Autodesk Fusion 360 part; units mm, degrees
(part 2 of 7)
sketch "Lower arm sketch" plane through (0, 0, 5) normal (0, 0, 1) x (1, 0, 0) in component "PRINT vertical alignment key B"
  line L0 (113, 68) -> (122, 68)
  line L1 (122, 68) -> (122, 72)
  line L2 (122, 72) -> (113, 72)
  line L3 (113, 72) -> (113, 68)
  dimension "d465" = 113
  dimension "d466" = 68
  dimension "d467" = 9
  dimension "d468" = 4
  constraint horizontal L0
  constraint vertical L1
  constraint horizontal L2
  constraint vertical L3
  measures "d465" horizontal distance of origin L0.start
  measures "d466" vertical distance of origin L0.start
  measures "d467" horizontal distance of L0.start L0.end
  measures "d468" vertical distance of L0.end L1.end
extrude "Lower arm" add sketch "Lower arm sketch" along normal blind 2 bodies 7 in component "PRINT vertical alignment key B"
ref_plane "WorkPlane3" through (0, 0, 5) normal (0, 0, 1) x (1, 0, 0) in component "PRINT vertical alignment key B"
sketch "Upper arm sketch" plane through (0, 0, 5) normal (0, 0, 1) x (1, 0, 0) in component "PRINT vertical alignment key B"
  line L0 (118, 78) -> (127, 78)
  line L1 (127, 78) -> (127, 82)
  line L2 (127, 82) -> (118, 82)
  line L3 (118, 82) -> (118, 78)
  dimension "d473" = 118
  dimension "d474" = 78
  dimension "d475" = 9
  dimension "d476" = 4
  constraint horizontal L0
  constraint vertical L1
  constraint horizontal L2
  constraint vertical L3
  measures "d473" horizontal distance of origin L0.start
  measures "d474" vertical distance of origin L0.start
  measures "d475" horizontal distance of L0.start L0.end
  measures "d476" vertical distance of L0.end L1.end
extrude "Upper arm" add sketch "Upper arm sketch" along normal blind 2 bodies 7 in component "PRINT vertical alignment key B"
ref_plane "WorkPlane4" through (0, 0, 5) normal (0, 0, 1) x (1, 0, 0) in component "PRINT vertical alignment key B"
sketch "Locating peg sketch (3)" plane through (0, 0, 5) normal (0, 0, 1) x (1, 0, 0) in component "PRINT vertical alignment key B"
  circle A0 centre (115, 70) radius 1.5
  dimension "d481" = 115
  dimension "d482" = 70
  dimension "d483" = 3
  measures "d481" horizontal distance of origin A0.centre
  measures "d482" vertical distance of origin A0.centre
  measures "d483" diameter of A0
extrude "Locating peg''" add sketch "Locating peg sketch (3)" against normal blind 0.8 bodies 7 in component "PRINT vertical alignment key B"
ref_plane "WorkPlane5" through (0, 0, 5) normal (0, 0, 1) x (1, 0, 0) in component "PRINT vertical alignment key B"
sketch "Locating peg sketch (1) (3)" plane through (0, 0, 5) normal (0, 0, 1) x (1, 0, 0) in component "PRINT vertical alignment key B"
  circle A0 centre (125, 80) radius 1.5
  dimension "d488" = 125
  dimension "d489" = 80
  dimension "d490" = 3
  measures "d488" horizontal distance of origin A0.centre
  measures "d489" vertical distance of origin A0.centre
  measures "d490" diameter of A0
extrude "Locating peg (1)''" add sketch "Locating peg sketch (1) (3)" against normal blind 0.8 bodies 7 in component "PRINT vertical alignment key B"
ref_plane "WorkPlane1" through (0, 0, 5) normal (0, 0, 1) x (1, 0, 0) in component "PRINT vertical alignment key T"
sketch "Key spine sketch (2)" plane through (0, 0, 5) normal (0, 0, 1) x (1, 0, 0) in component "PRINT vertical alignment key T"
  line L0 (118, 188) -> (122, 188)
  line L1 (122, 188) -> (122, 202)
  line L2 (122, 202) -> (118, 202)
  line L3 (118, 202) -> (118, 188)
  dimension "d495" = 118
  dimension "d496" = 188
  dimension "d497" = 4
  dimension "d498" = 14
  constraint horizontal L0
  constraint vertical L1
  constraint horizontal L2
  constraint vertical L3
  measures "d495" horizontal distance of origin L0.start
  measures "d496" vertical distance of origin L0.start
  measures "d497" horizontal distance of L0.start L0.end
  measures "d498" vertical distance of L0.end L1.end
extrude "Key spine'" add sketch "Key spine sketch (2)" along normal blind 2 separate body makes body 8 in component "PRINT vertical alignment key T"
ref_plane "WorkPlane2" through (0, 0, 5) normal (0, 0, 1) x (1, 0, 0) in component "PRINT vertical alignment key T"
sketch "Lower arm sketch (2)" plane through (0, 0, 5) normal (0, 0, 1) x (1, 0, 0) in component "PRINT vertical alignment key T"
  line L0 (113, 188) -> (122, 188)
  line L1 (122, 188) -> (122, 192)
  line L2 (122, 192) -> (113, 192)
  line L3 (113, 192) -> (113, 188)
  dimension "d503" = 113
  dimension "d504" = 188
  dimension "d505" = 9
  dimension "d506" = 4
  constraint horizontal L0
  constraint vertical L1
  constraint horizontal L2
  constraint vertical L3
  measures "d503" horizontal distance of origin L0.start
  measures "d504" vertical distance of origin L0.start
  measures "d505" horizontal distance of L0.start L0.end
  measures "d506" vertical distance of L0.end L1.end
extrude "Lower arm'" add sketch "Lower arm sketch (2)" along normal blind 2 bodies 8 in component "PRINT vertical alignment key T"
ref_plane "WorkPlane3" through (0, 0, 5) normal (0, 0, 1) x (1, 0, 0) in component "PRINT vertical alignment key T"
sketch "Upper arm sketch (2)" plane through (0, 0, 5) normal (0, 0, 1) x (1, 0, 0) in component "PRINT vertical alignment key T"
  line L0 (118, 198) -> (127, 198)
  line L1 (127, 198) -> (127, 202)
  line L2 (127, 202) -> (118, 202)
  line L3 (118, 202) -> (118, 198)
  dimension "d511" = 118
  dimension "d512" = 198
  dimension "d513" = 9
  dimension "d514" = 4
  constraint horizontal L0
  constraint vertical L1
  constraint horizontal L2
  constraint vertical L3
  measures "d511" horizontal distance of origin L0.start
  measures "d512" vertical distance of origin L0.start
  measures "d513" horizontal distance of L0.start L0.end
  measures "d514" vertical distance of L0.end L1.end
extrude "Upper arm'" add sketch "Upper arm sketch (2)" along normal blind 2 bodies 8 in component "PRINT vertical alignment key T"
ref_plane "WorkPlane4" through (0, 0, 5) normal (0, 0, 1) x (1, 0, 0) in component "PRINT vertical alignment key T"
sketch "Locating peg sketch (4)" plane through (0, 0, 5) normal (0, 0, 1) x (1, 0, 0) in component "PRINT vertical alignment key T"
  circle A0 centre (115, 190) radius 1.5
  dimension "d519" = 115
  dimension "d520" = 190
  dimension "d521" = 3
  measures "d519" horizontal distance of origin A0.centre
  measures "d520" vertical distance of origin A0.centre
  measures "d521" diameter of A0
extrude "Locating peg'''" add sketch "Locating peg sketch (4)" against normal blind 0.8 bodies 8 in component "PRINT vertical alignment key T"
ref_plane "WorkPlane5" through (0, 0, 5) normal (0, 0, 1) x (1, 0, 0) in component "PRINT vertical alignment key T"
sketch "Locating peg sketch (1) (4)" plane through (0, 0, 5) normal (0, 0, 1) x (1, 0, 0) in component "PRINT vertical alignment key T"
  circle A0 centre (125, 200) radius 1.5
  dimension "d526" = 125
  dimension "d527" = 200
  dimension "d528" = 3
  measures "d526" horizontal distance of origin A0.centre
  measures "d527" vertical distance of origin A0.centre
  measures "d528" diameter of A0
extrude "Locating peg (1)'''" add sketch "Locating peg sketch (1) (4)" against normal blind 0.8 bodies 8 in component "PRINT vertical alignment key T"
ref_plane "WorkPlane1" through (0, 0, 15) normal (0, 0, 1) x (1, 0, 0) in component "Vertical rail 0 - nominal 2020 slot-6 envelope"
sketch "Extrusion envelope sketch" plane through (0, 0, 15) normal (0, 0, 1) x (1, 0, 0) in component "Vertical rail 0 - nominal 2020 slot-6 envelope"
  line L0 (2, 2) -> (22, 2)
  line L1 (22, 2) -> (22, 238)
  line L2 (22, 238) -> (2, 238)
  line L3 (2, 238) -> (2, 2)
  dimension "d533" = 2
  dimension "d534" = 2
  dimension "d535" = 20
  dimension "d536" = 236
  constraint horizontal L0
  constraint vertical L1
  constraint horizontal L2
  constraint vertical L3
  measures "d533" horizontal distance of origin L0.start
  measures "d534" vertical distance of origin L0.start
  measures "d535" horizontal distance of L0.start L0.end
  measures "d536" vertical distance of L0.end L1.end
extrude "Extrusion envelope" add sketch "Extrusion envelope sketch" along normal blind 20 separate body makes body 9 in component "Vertical rail 0 - nominal 2020 slot-6 envelope"
ref_plane "WorkPlane2" through (0, 0, 15) normal (0, 0, 1) x (1, 0, 0) in component "Vertical rail 0 - nominal 2020 slot-6 envelope"
sketch "Front slot mouth sketch" plane through (0, 0, 15) normal (0, 0, 1) x (1, 0, 0) in component "Vertical rail 0 - nominal 2020 slot-6 envelope"
  line L0 (9, 2) -> (15, 2)
  line L1 (15, 2) -> (15, 238)
  line L2 (15, 238) -> (9, 238)
  line L3 (9, 238) -> (9, 2)
  dimension "d541" = 9
  dimension "d542" = 2
  dimension "d543" = 6
  dimension "d544" = 236
  constraint horizontal L0
  constraint vertical L1
  constraint horizontal L2
  constraint vertical L3
  measures "d541" horizontal distance of origin L0.start
  measures "d542" vertical distance of origin L0.start
  measures "d543" horizontal distance of L0.start L0.end
  measures "d544" vertical distance of L0.end L1.end
extrude "Front slot mouth" cut sketch "Front slot mouth sketch" along normal blind 1.8 bodies 9 in component "Vertical rail 0 - nominal 2020 slot-6 envelope"
ref_plane "WorkPlane3" through (0, 0, 16.8) normal (0, 0, 1) x (1, 0, 0) in component "Vertical rail 0 - nominal 2020 slot-6 envelope"
sketch "T nut channel sketch" plane through (0, 0, 16.8) normal (0, 0, 1) x (1, 0, 0) in component "Vertical rail 0 - nominal 2020 slot-6 envelope"
  line L0 (7, 2) -> (17, 2)
  line L1 (17, 2) -> (17, 238)
  line L2 (17, 238) -> (7, 238)
  line L3 (7, 238) -> (7, 2)
  dimension "d549" = 7
  dimension "d550" = 2
  dimension "d551" = 10
  dimension "d552" = 236
  constraint horizontal L0
  constraint vertical L1
  constraint horizontal L2
  constraint vertical L3
  measures "d549" horizontal distance of origin L0.start
  measures "d550" vertical distance of origin L0.start
  measures "d551" horizontal distance of L0.start L0.end
  measures "d552" vertical distance of L0.end L1.end
extrude "T nut channel" cut sketch "T nut channel sketch" along normal blind 4.2 bodies 9 in component "Vertical rail 0 - nominal 2020 slot-6 envelope"
ref_plane "WorkPlane1" through (0, 0, 15) normal (0, 0, 1) x (1, 0, 0) in component "Vertical rail 1 - nominal 2020 slot-6 envelope"
sketch "Extrusion envelope sketch (2)" plane through (0, 0, 15) normal (0, 0, 1) x (1, 0, 0) in component "Vertical rail 1 - nominal 2020 slot-6 envelope"
  line L0 (110, 2) -> (130, 2)
  line L1 (130, 2) -> (130, 238)
  line L2 (130, 238) -> (110, 238)
  line L3 (110, 238) -> (110, 2)
  dimension "d557" = 110
  dimension "d558" = 2
  dimension "d559" = 20
  dimension "d560" = 236
  constraint horizontal L0
  constraint vertical L1
  constraint horizontal L2
  constraint vertical L3
  measures "d557" horizontal distance of origin L0.start
  measures "d558" vertical distance of origin L0.start
  measures "d559" horizontal distance of L0.start L0.end
  measures "d560" vertical distance of L0.end L1.end
extrude "Extrusion envelope'" add sketch "Extrusion envelope sketch (2)" along normal blind 20 separate body makes body 10 in component "Vertical rail 1 - nominal 2020 slot-6 envelope"
ref_plane "WorkPlane2" through (0, 0, 15) normal (0, 0, 1) x (1, 0, 0) in component "Vertical rail 1 - nominal 2020 slot-6 envelope"
sketch "Front slot mouth sketch (2)" plane through (0, 0, 15) normal (0, 0, 1) x (1, 0, 0) in component "Vertical rail 1 - nominal 2020 slot-6 envelope"
  line L0 (117, 2) -> (123, 2)
  line L1 (123, 2) -> (123, 238)
  line L2 (123, 238) -> (117, 238)
  line L3 (117, 238) -> (117, 2)
  dimension "d565" = 117
  dimension "d566" = 2
  dimension "d567" = 6
  dimension "d568" = 236
  constraint horizontal L0
  constraint vertical L1
  constraint horizontal L2
  constraint vertical L3
  measures "d565" horizontal distance of origin L0.start
  measures "d566" vertical distance of origin L0.start
  measures "d567" horizontal distance of L0.start L0.end
  measures "d568" vertical distance of L0.end L1.end
extrude "Front slot mouth'" cut sketch "Front slot mouth sketch (2)" along normal blind 1.8 bodies 10 in component "Vertical rail 1 - nominal 2020 slot-6 envelope"
ref_plane "WorkPlane3" through (0, 0, 16.8) normal (0, 0, 1) x (1, 0, 0) in component "Vertical rail 1 - nominal 2020 slot-6 envelope"
sketch "T nut channel sketch (2)" plane through (0, 0, 16.8) normal (0, 0, 1) x (1, 0, 0) in component "Vertical rail 1 - nominal 2020 slot-6 envelope"
  line L0 (115, 2) -> (125, 2)
  line L1 (125, 2) -> (125, 238)
  line L2 (125, 238) -> (115, 238)
  line L3 (115, 238) -> (115, 2)
  dimension "d573" = 115
  dimension "d574" = 2
  dimension "d575" = 10
  dimension "d576" = 236
  constraint horizontal L0
  constraint vertical L1
  constraint horizontal L2
  constraint vertical L3
  measures "d573" horizontal distance of origin L0.start
  measures "d574" vertical distance of origin L0.start
  measures "d575" horizontal distance of L0.start L0.end
  measures "d576" vertical distance of L0.end L1.end
extrude "T nut channel'" cut sketch "T nut channel sketch (2)" along normal blind 4.2 bodies 10 in component "Vertical rail 1 - nominal 2020 slot-6 envelope"
ref_plane "WorkPlane1" through (0, 0, 15) normal (0, 0, 1) x (1, 0, 0) in component "Vertical rail 2 - nominal 2020 slot-6 envelope"
sketch "Extrusion envelope sketch (3)" plane through (0, 0, 15) normal (0, 0, 1) x (1, 0, 0) in component "Vertical rail 2 - nominal 2020 slot-6 envelope"
  line L0 (218, 2) -> (238, 2)
  line L1 (238, 2) -> (238, 238)
  line L2 (238, 238) -> (218, 238)
  line L3 (218, 238) -> (218, 2)
  dimension "d581" = 218
  dimension "d582" = 2
  dimension "d583" = 20
  dimension "d584" = 236
  constraint horizontal L0
  constraint vertical L1
  constraint horizontal L2
  constraint vertical L3
  measures "d581" horizontal distance of origin L0.start
  measures "d582" vertical distance of origin L0.start
  measures "d583" horizontal distance of L0.start L0.end
  measures "d584" vertical distance of L0.end L1.end
extrude "Extrusion envelope''" add sketch "Extrusion envelope sketch (3)" along normal blind 20 separate body makes body 11 in component "Vertical rail 2 - nominal 2020 slot-6 envelope"
ref_plane "WorkPlane2" through (0, 0, 15) normal (0, 0, 1) x (1, 0, 0) in component "Vertical rail 2 - nominal 2020 slot-6 envelope"
sketch "Front slot mouth sketch (3)" plane through (0, 0, 15) normal (0, 0, 1) x (1, 0, 0) in component "Vertical rail 2 - nominal 2020 slot-6 envelope"
  line L0 (225, 2) -> (231, 2)
  line L1 (231, 2) -> (231, 238)
  line L2 (231, 238) -> (225, 238)
  line L3 (225, 238) -> (225, 2)
  dimension "d589" = 225
  dimension "d590" = 2
  dimension "d591" = 6
  dimension "d592" = 236
  constraint horizontal L0
  constraint vertical L1
  constraint horizontal L2
  constraint vertical L3
  measures "d589" horizontal distance of origin L0.start
  measures "d590" vertical distance of origin L0.start
  measures "d591" horizontal distance of L0.start L0.end
  measures "d592" vertical distance of L0.end L1.end
extrude "Front slot mouth''" cut sketch "Front slot mouth sketch (3)" along normal blind 1.8 bodies 11 in component "Vertical rail 2 - nominal 2020 slot-6 envelope"
ref_plane "WorkPlane3" through (0, 0, 16.8) normal (0, 0, 1) x (1, 0, 0) in component "Vertical rail 2 - nominal 2020 slot-6 envelope"
sketch "T nut channel sketch (3)" plane through (0, 0, 16.8) normal (0, 0, 1) x (1, 0, 0) in component "Vertical rail 2 - nominal 2020 slot-6 envelope"
  line L0 (223, 2) -> (233, 2)
  line L1 (233, 2) -> (233, 238)
  line L2 (233, 238) -> (223, 238)
  line L3 (223, 238) -> (223, 2)
  dimension "d597" = 223
  dimension "d598" = 2
  dimension "d599" = 10
  dimension "d600" = 236
  constraint horizontal L0
  constraint vertical L1
  constraint horizontal L2
  constraint vertical L3
  measures "d597" horizontal distance of origin L0.start
  measures "d598" vertical distance of origin L0.start
  measures "d599" horizontal distance of L0.start L0.end
  measures "d600" vertical distance of L0.end L1.end
extrude "T nut channel''" cut sketch "T nut channel sketch (3)" along normal blind 4.2 bodies 11 in component "Vertical rail 2 - nominal 2020 slot-6 envelope"
ref_plane "WorkPlane1" through (0, 0, 15) normal (0, 0, 1) x (1, 0, 0) in component "Horizontal tie 00 - nominal 2020 slot-6 envelope"
sketch "Extrusion envelope sketch (4)" plane through (0, 0, 15) normal (0, 0, 1) x (1, 0, 0) in component "Horizontal tie 00 - nominal 2020 slot-6 envelope"
  line L0 (22, 2) -> (110, 2)
  line L1 (110, 2) -> (110, 22)
  line L2 (110, 22) -> (22, 22)
  line L3 (22, 22) -> (22, 2)
  dimension "d605" = 22
  dimension "d606" = 2
  dimension "d607" = 88
  dimension "d608" = 20
  constraint horizontal L0
  constraint vertical L1
  constraint horizontal L2
  constraint vertical L3
  measures "d605" horizontal distance of origin L0.start
  measures "d606" vertical distance of origin L0.start
  measures "d607" horizontal distance of L0.start L0.end
  measures "d608" vertical distance of L0.end L1.end
extrude "Extrusion envelope'''" add sketch "Extrusion envelope sketch (4)" along normal blind 20 separate body makes body 12 in component "Horizontal tie 00 - nominal 2020 slot-6 envelope"
ref_plane "WorkPlane2" through (0, 0, 15) normal (0, 0, 1) x (1, 0, 0) in component "Horizontal tie 00 - nominal 2020 slot-6 envelope"
sketch "Front slot mouth sketch (4)" plane through (0, 0, 15) normal (0, 0, 1) x (1, 0, 0) in component "Horizontal tie 00 - nominal 2020 slot-6 envelope"
  line L0 (22, 9) -> (110, 9)
  line L1 (110, 9) -> (110, 15)
  line L2 (110, 15) -> (22, 15)
  line L3 (22, 15) -> (22, 9)
  dimension "d613" = 22
  dimension "d614" = 9
  dimension "d615" = 88
  dimension "d616" = 6
  constraint horizontal L0
  constraint vertical L1
  constraint horizontal L2
  constraint vertical L3
  measures "d613" horizontal distance of origin L0.start
  measures "d614" vertical distance of origin L0.start
  measures "d615" horizontal distance of L0.start L0.end
  measures "d616" vertical distance of L0.end L1.end
extrude "Front slot mouth'''" cut sketch "Front slot mouth sketch (4)" along normal blind 1.8 bodies 12 in component "Horizontal tie 00 - nominal 2020 slot-6 envelope"
ref_plane "WorkPlane3" through (0, 0, 16.8) normal (0, 0, 1) x (1, 0, 0) in component "Horizontal tie 00 - nominal 2020 slot-6 envelope"
sketch "T nut channel sketch (4)" plane through (0, 0, 16.8) normal (0, 0, 1) x (1, 0, 0) in component "Horizontal tie 00 - nominal 2020 slot-6 envelope"
  line L0 (22, 7) -> (110, 7)
  line L1 (110, 7) -> (110, 17)
  line L2 (110, 17) -> (22, 17)
  line L3 (22, 17) -> (22, 7)
  dimension "d621" = 22
  dimension "d622" = 7
  dimension "d623" = 88
  dimension "d624" = 10
  constraint horizontal L0
  constraint vertical L1
  constraint horizontal L2
  constraint vertical L3
  measures "d621" horizontal distance of origin L0.start
  measures "d622" vertical distance of origin L0.start
  measures "d623" horizontal distance of L0.start L0.end
  measures "d624" vertical distance of L0.end L1.end
extrude "T nut channel'''" cut sketch "T nut channel sketch (4)" along normal blind 4.2 bodies 12 in component "Horizontal tie 00 - nominal 2020 slot-6 envelope"
ref_plane "WorkPlane1" through (0, 0, 15) normal (0, 0, 1) x (1, 0, 0) in component "Horizontal tie 10 - nominal 2020 slot-6 envelope"
sketch "Extrusion envelope sketch (5)" plane through (0, 0, 15) normal (0, 0, 1) x (1, 0, 0) in component "Horizontal tie 10 - nominal 2020 slot-6 envelope"
  line L0 (130, 2) -> (218, 2)
  line L1 (218, 2) -> (218, 22)
  line L2 (218, 22) -> (130, 22)
  line L3 (130, 22) -> (130, 2)
  dimension "d629" = 130
  dimension "d630" = 2
  dimension "d631" = 88
  dimension "d632" = 20
  constraint horizontal L0
  constraint vertical L1
  constraint horizontal L2
  constraint vertical L3
  measures "d629" horizontal distance of origin L0.start
  measures "d630" vertical distance of origin L0.start
  measures "d631" horizontal distance of L0.start L0.end
  measures "d632" vertical distance of L0.end L1.end
extrude "Extrusion envelope''''" add sketch "Extrusion envelope sketch (5)" along normal blind 20 separate body makes body 13 in component "Horizontal tie 10 - nominal 2020 slot-6 envelope"
ref_plane "WorkPlane2" through (0, 0, 15) normal (0, 0, 1) x (1, 0, 0) in component "Horizontal tie 10 - nominal 2020 slot-6 envelope"
sketch "Front slot mouth sketch (5)" plane through (0, 0, 15) normal (0, 0, 1) x (1, 0, 0) in component "Horizontal tie 10 - nominal 2020 slot-6 envelope"
  line L0 (130, 9) -> (218, 9)
  line L1 (218, 9) -> (218, 15)
  line L2 (218, 15) -> (130, 15)
  line L3 (130, 15) -> (130, 9)
  dimension "d637" = 130
  dimension "d638" = 9
  dimension "d639" = 88
  dimension "d640" = 6
  constraint horizontal L0
  constraint vertical L1
  constraint horizontal L2
  constraint vertical L3
  measures "d637" horizontal distance of origin L0.start
  measures "d638" vertical distance of origin L0.start
  measures "d639" horizontal distance of L0.start L0.end
  measures "d640" vertical distance of L0.end L1.end
extrude "Front slot mouth''''" cut sketch "Front slot mouth sketch (5)" along normal blind 1.8 bodies 13 in component "Horizontal tie 10 - nominal 2020 slot-6 envelope"
ref_plane "WorkPlane3" through (0, 0, 16.8) normal (0, 0, 1) x (1, 0, 0) in component "Horizontal tie 10 - nominal 2020 slot-6 envelope"
sketch "T nut channel sketch (5)" plane through (0, 0, 16.8) normal (0, 0, 1) x (1, 0, 0) in component "Horizontal tie 10 - nominal 2020 slot-6 envelope"
  line L0 (130, 7) -> (218, 7)
  line L1 (218, 7) -> (218, 17)
  line L2 (218, 17) -> (130, 17)
  line L3 (130, 17) -> (130, 7)
  dimension "d645" = 130
  dimension "d646" = 7
  dimension "d647" = 88
  dimension "d648" = 10
  constraint horizontal L0
  constraint vertical L1
  constraint horizontal L2
  constraint vertical L3
  measures "d645" horizontal distance of origin L0.start
  measures "d646" vertical distance of origin L0.start
  measures "d647" horizontal distance of L0.start L0.end
  measures "d648" vertical distance of L0.end L1.end
extrude "T nut channel''''" cut sketch "T nut channel sketch (5)" along normal blind 4.2 bodies 13 in component "Horizontal tie 10 - nominal 2020 slot-6 envelope"
ref_plane "WorkPlane1" through (0, 0, 15) normal (0, 0, 1) x (1, 0, 0) in component "Horizontal tie 01 - nominal 2020 slot-6 envelope"
sketch "Extrusion envelope sketch (6)" plane through (0, 0, 15) normal (0, 0, 1) x (1, 0, 0) in component "Horizontal tie 01 - nominal 2020 slot-6 envelope"
  line L0 (22, 218) -> (110, 218)
  line L1 (110, 218) -> (110, 238)
  line L2 (110, 238) -> (22, 238)
  line L3 (22, 238) -> (22, 218)
  dimension "d653" = 22
  dimension "d654" = 218
  dimension "d655" = 88
  dimension "d656" = 20
  constraint horizontal L0
  constraint vertical L1
  constraint horizontal L2
  constraint vertical L3
  measures "d653" horizontal distance of origin L0.start
  measures "d654" vertical distance of origin L0.start
  measures "d655" horizontal distance of L0.start L0.end
  measures "d656" vertical distance of L0.end L1.end
extrude "Extrusion envelope'''''" add sketch "Extrusion envelope sketch (6)" along normal blind 20 separate body makes body 14 in component "Horizontal tie 01 - nominal 2020 slot-6 envelope"
ref_plane "WorkPlane2" through (0, 0, 15) normal (0, 0, 1) x (1, 0, 0) in component "Horizontal tie 01 - nominal 2020 slot-6 envelope"
sketch "Front slot mouth sketch (6)" plane through (0, 0, 15) normal (0, 0, 1) x (1, 0, 0) in component "Horizontal tie 01 - nominal 2020 slot-6 envelope"
  line L0 (22, 225) -> (110, 225)
  line L1 (110, 225) -> (110, 231)
  line L2 (110, 231) -> (22, 231)
  line L3 (22, 231) -> (22, 225)
  dimension "d661" = 22
  dimension "d662" = 225
  dimension "d663" = 88
  dimension "d664" = 6
  constraint horizontal L0
  constraint vertical L1
  constraint horizontal L2
  constraint vertical L3
  measures "d661" horizontal distance of origin L0.start
  measures "d662" vertical distance of origin L0.start
  measures "d663" horizontal distance of L0.start L0.end
  measures "d664" vertical distance of L0.end L1.end
extrude "Front slot mouth'''''" cut sketch "Front slot mouth sketch (6)" along normal blind 1.8 bodies 14 in component "Horizontal tie 01 - nominal 2020 slot-6 envelope"
ref_plane "WorkPlane3" through (0, 0, 16.8) normal (0, 0, 1) x (1, 0, 0) in component "Horizontal tie 01 - nominal 2020 slot-6 envelope"
sketch "T nut channel sketch (6)" plane through (0, 0, 16.8) normal (0, 0, 1) x (1, 0, 0) in component "Horizontal tie 01 - nominal 2020 slot-6 envelope"
  line L0 (22, 223) -> (110, 223)
  line L1 (110, 223) -> (110, 233)
  line L2 (110, 233) -> (22, 233)
  line L3 (22, 233) -> (22, 223)
  dimension "d669" = 22
  dimension "d670" = 223
  dimension "d671" = 88
  dimension "d672" = 10
  constraint horizontal L0
  constraint vertical L1
  constraint horizontal L2
  constraint vertical L3
  measures "d669" horizontal distance of origin L0.start
  measures "d670" vertical distance of origin L0.start
  measures "d671" horizontal distance of L0.start L0.end
  measures "d672" vertical distance of L0.end L1.end
extrude "T nut channel'''''" cut sketch "T nut channel sketch (6)" along normal blind 4.2 bodies 14 in component "Horizontal tie 01 - nominal 2020 slot-6 envelope"
ref_plane "WorkPlane1" through (0, 0, 15) normal (0, 0, 1) x (1, 0, 0) in component "Horizontal tie 11 - nominal 2020 slot-6 envelope"
sketch "Extrusion envelope sketch (7)" plane through (0, 0, 15) normal (0, 0, 1) x (1, 0, 0) in component "Horizontal tie 11 - nominal 2020 slot-6 envelope"
  line L0 (130, 218) -> (218, 218)
  line L1 (218, 218) -> (218, 238)
  line L2 (218, 238) -> (130, 238)
  line L3 (130, 238) -> (130, 218)
  dimension "d677" = 130
  dimension "d678" = 218
  dimension "d679" = 88
  dimension "d680" = 20
  constraint horizontal L0
  constraint vertical L1
  constraint horizontal L2
  constraint vertical L3
  measures "d677" horizontal distance of origin L0.start
  measures "d678" vertical distance of origin L0.start
  measures "d679" horizontal distance of L0.start L0.end
  measures "d680" vertical distance of L0.end L1.end
extrude "Extrusion envelope''''''" add sketch "Extrusion envelope sketch (7)" along normal blind 20 separate body makes body 15 in component "Horizontal tie 11 - nominal 2020 slot-6 envelope"
ref_plane "WorkPlane2" through (0, 0, 15) normal (0, 0, 1) x (1, 0, 0) in component "Horizontal tie 11 - nominal 2020 slot-6 envelope"
sketch "Front slot mouth sketch (7)" plane through (0, 0, 15) normal (0, 0, 1) x (1, 0, 0) in component "Horizontal tie 11 - nominal 2020 slot-6 envelope"
  line L0 (130, 225) -> (218, 225)
  line L1 (218, 225) -> (218, 231)
  line L2 (218, 231) -> (130, 231)
  line L3 (130, 231) -> (130, 225)
  dimension "d685" = 130
  dimension "d686" = 225
  dimension "d687" = 88
  dimension "d688" = 6
  constraint horizontal L0
  constraint vertical L1
  constraint horizontal L2
  constraint vertical L3
  measures "d685" horizontal distance of origin L0.start
  measures "d686" vertical distance of origin L0.start
  measures "d687" horizontal distance of L0.start L0.end
  measures "d688" vertical distance of L0.end L1.end
extrude "Front slot mouth''''''" cut sketch "Front slot mouth sketch (7)" along normal blind 1.8 bodies 15 in component "Horizontal tie 11 - nominal 2020 slot-6 envelope"
ref_plane "WorkPlane3" through (0, 0, 16.8) normal (0, 0, 1) x (1, 0, 0) in component "Horizontal tie 11 - nominal 2020 slot-6 envelope"
sketch "T nut channel sketch (7)" plane through (0, 0, 16.8) normal (0, 0, 1) x (1, 0, 0) in component "Horizontal tie 11 - nominal 2020 slot-6 envelope"
  line L0 (130, 223) -> (218, 223)
  line L1 (218, 223) -> (218, 233)
  line L2 (218, 233) -> (130, 233)
  line L3 (130, 233) -> (130, 223)
  dimension "d693" = 130
  dimension "d694" = 223
  dimension "d695" = 88
  dimension "d696" = 10
  constraint horizontal L0
  constraint vertical L1
  constraint horizontal L2
  constraint vertical L3
  measures "d693" horizontal distance of origin L0.start
  measures "d694" vertical distance of origin L0.start
  measures "d695" horizontal distance of L0.start L0.end
  measures "d696" vertical distance of L0.end L1.end
extrude "T nut channel''''''" cut sketch "T nut channel sketch (7)" along normal blind 4.2 bodies 15 in component "Horizontal tie 11 - nominal 2020 slot-6 envelope"
ref_plane "WorkPlane1" through (0, 0, -2) normal (0, 0, 1) x (1, 0, 0) in component "METAL cap 00"
sketch "Visible cap sketch" plane through (0, 0, -2) normal (0, 0, 1) x (1, 0, 0) in component "METAL cap 00"
  circle A0 centre (12, 12) radius 9
  dimension "d701" = 12
  dimension "d702" = 12
  dimension "d703" = 18
  measures "d701" horizontal distance of origin A0.centre
  measures "d702" vertical distance of origin A0.centre
  measures "d703" diameter of A0
extrude "Visible cap" add sketch "Visible cap sketch" along normal blind 2 separate body makes body 16 in component "METAL cap 00"
ref_plane "WorkPlane2" through (0, 0, -2) normal (0, 0, 1) x (1, 0, 0) in component "METAL cap 00"
sketch "M5 clearance sketch" plane through (0, 0, -2) normal (0, 0, 1) x (1, 0, 0) in component "METAL cap 00"
  circle A0 centre (12, 12) radius 2.75
  dimension "d708" = 12
  dimension "d709" = 12
  dimension "d710" = 5.5
  measures "d708" horizontal distance of origin A0.centre
  measures "d709" vertical distance of origin A0.centre
  measures "d710" diameter of A0
extrude "M5 clearance" cut sketch "M5 clearance sketch" along normal blind 2 bodies 16 in component "METAL cap 00"
ref_plane "WorkPlane1" through (0, 0, 5) normal (0, 0, 1) x (1, 0, 0) in component "PRINT rear bearing seat 00"
sketch "Rear bearing seat sketch" plane through (0, 0, 5) normal (0, 0, 1) x (1, 0, 0) in component "PRINT rear bearing seat 00"
  circle A0 centre (12, 12) radius 9
  dimension "d715" = 12
  dimension "d716" = 12
  dimension "d717" = 18
  measures "d715" horizontal distance of origin A0.centre
  measures "d716" vertical distance of origin A0.centre
  measures "d717" diameter of A0
extrude "Rear bearing seat" add sketch "Rear bearing seat sketch" along normal blind 2 separate body makes body 17 in component "PRINT rear bearing seat 00"
ref_plane "WorkPlane2" through (0, 0, 5) normal (0, 0, 1) x (1, 0, 0) in component "PRINT rear bearing seat 00"
sketch "Shoulder clearance sketch" plane through (0, 0, 5) normal (0, 0, 1) x (1, 0, 0) in component "PRINT rear bearing seat 00"
  circle A0 centre (12, 12) radius 4.2
  dimension "d722" = 12
  dimension "d723" = 12
  dimension "d724" = 8.4
  measures "d722" horizontal distance of origin A0.centre
  measures "d723" vertical distance of origin A0.centre
  measures "d724" diameter of A0
extrude "Shoulder clearance" cut sketch "Shoulder clearance sketch" along normal blind 2 bodies 17 in component "PRINT rear bearing seat 00"
sketch "8 mm shoulder sketch" plane through (0, 0, 0) normal (0, 0, 1) x (1, 0, 0) in component "METAL stepped compression spacer 00"
  circle A0 centre (12, 12) radius 4
  dimension "d727" = 12
  dimension "d728" = 12
  dimension "d729" = 8
  measures "d727" horizontal distance of origin A0.centre
  measures "d728" vertical distance of origin A0.centre
  measures "d729" diameter of A0
extrude "8 mm shoulder" add sketch "8 mm shoulder sketch" along normal blind 7 separate body makes body 18 in component "METAL stepped compression spacer 00"
ref_plane "WorkPlane1" through (0, 0, 7) normal (0, 0, 1) x (1, 0, 0) in component "METAL stepped compression spacer 00"
sketch "12 mm base sketch" plane through (0, 0, 7) normal (0, 0, 1) x (1, 0, 0) in component "METAL stepped compression spacer 00"
  circle A0 centre (12, 12) radius 6
  dimension "d734" = 12
  dimension "d735" = 12
  dimension "d736" = 12
  measures "d734" horizontal distance of origin A0.centre
  measures "d735" vertical distance of origin A0.centre
  measures "d736" diameter of A0
extrude "12 mm base" add sketch "12 mm base sketch" along normal blind 8 bodies 18 in component "METAL stepped compression spacer 00"
sketch "Through bore sketch" plane through (0, 0, 0) normal (0, 0, 1) x (1, 0, 0) in component "METAL stepped compression spacer 00"
  circle A0 centre (12, 12) radius 2.75
  dimension "d739" = 12
  dimension "d740" = 12
  dimension "d741" = 5.5
  measures "d739" horizontal distance of origin A0.centre
  measures "d740" vertical distance of origin A0.centre
  measures "d741" diameter of A0
extrude "Through bore" cut sketch "Through bore sketch" along normal blind 15 bodies 18 in component "METAL stepped compression spacer 00"
ref_plane "WorkPlane1" through (0, 0, -5) normal (0, 0, 1) x (1, 0, 0) in component "REFERENCE M5 screw 00 - length follows stack"
sketch "Nominal button head sketch" plane through (0, 0, -5) normal (0, 0, 1) x (1, 0, 0) in component "REFERENCE M5 screw 00 - length follows stack"
  circle A0 centre (12, 12) radius 4.75
  dimension "d746" = 12
  dimension "d747" = 12
  dimension "d748" = 9.5
  measures "d746" horizontal distance of origin A0.centre
  measures "d747" vertical distance of origin A0.centre
  measures "d748" diameter of A0
extrude "Nominal button head" add sketch "Nominal button head sketch" along normal blind 3 separate body makes body 19 in component "REFERENCE M5 screw 00 - length follows stack"
ref_plane "WorkPlane2" through (0, 0, -2) normal (0, 0, 1) x (1, 0, 0) in component "REFERENCE M5 screw 00 - length follows stack"
sketch "Unthreaded shank envelope sketch" plane through (0, 0, -2) normal (0, 0, 1) x (1, 0, 0) in component "REFERENCE M5 screw 00 - length follows stack"
  circle A0 centre (12, 12) radius 2.5
  dimension "d753" = 12
  dimension "d754" = 12
  dimension "d755" = 5
  measures "d753" horizontal distance of origin A0.centre
  measures "d754" vertical distance of origin A0.centre
  measures "d755" diameter of A0
extrude "Unthreaded shank envelope" add sketch "Unthreaded shank envelope sketch" along normal blind 22 bodies 19 in component "REFERENCE M5 screw 00 - length follows stack"
ref_plane "WorkPlane1" through (0, 0, 17) normal (0, 0, 1) x (1, 0, 0) in component "REFERENCE M5 slot-6 T nut 00"
sketch "T nut envelope sketch" plane through (0, 0, 17) normal (0, 0, 1) x (1, 0, 0) in component "REFERENCE M5 slot-6 T nut 00"
  line L0 (7.2, 7) -> (16.8, 7)
  line L1 (16.8, 7) -> (16.8, 17)
  line L2 (16.8, 17) -> (7.2, 17)
  line L3 (7.2, 17) -> (7.2, 7)
  dimension "d760" = 7.2
  dimension "d761" = 7
  dimension "d762" = 9.6
  dimension "d763" = 10
  constraint horizontal L0
  constraint vertical L1
  constraint horizontal L2
  constraint vertical L3
  measures "d760" horizontal distance of origin L0.start
  measures "d761" vertical distance of origin L0.start
  measures "d762" horizontal distance of L0.start L0.end
  measures "d763" vertical distance of L0.end L1.end
extrude "T nut envelope" add sketch "T nut envelope sketch" along normal blind 4 separate body makes body 20 in component "REFERENCE M5 slot-6 T nut 00"
ref_plane "WorkPlane2" through (0, 0, 17) normal (0, 0, 1) x (1, 0, 0) in component "REFERENCE M5 slot-6 T nut 00"
sketch "Thread envelope sketch" plane through (0, 0, 17) normal (0, 0, 1) x (1, 0, 0) in component "REFERENCE M5 slot-6 T nut 00"
  circle A0 centre (12, 12) radius 2.6
  dimension "d768" = 12
  dimension "d769" = 12
  dimension "d770" = 5.2
  measures "d768" horizontal distance of origin A0.centre
  measures "d769" vertical distance of origin A0.centre
  measures "d770" diameter of A0
extrude "Thread envelope" cut sketch "Thread envelope sketch" along normal blind 4 bodies 19 in component "REFERENCE M5 screw 00 - length follows stack"
extrude "Extrude2" cut sketch "Thread envelope sketch" along normal blind 4 bodies 20 in component "REFERENCE M5 slot-6 T nut 00"
ref_plane "WorkPlane1" through (0, 0, -2) normal (0, 0, 1) x (1, 0, 0) in component "METAL cap 01"
sketch "Visible cap sketch (2)" plane through (0, 0, -2) normal (0, 0, 1) x (1, 0, 0) in component "METAL cap 01"
  circle A0 centre (12, 120) radius 9
  dimension "d777" = 12
  dimension "d778" = 120
  dimension "d779" = 18
  measures "d777" horizontal distance of origin A0.centre
  measures "d778" vertical distance of origin A0.centre
  measures "d779" diameter of A0
extrude "Visible cap'" add sketch "Visible cap sketch (2)" along normal blind 2 separate body makes body 21 in component "METAL cap 01"
ref_plane "WorkPlane2" through (0, 0, -2) normal (0, 0, 1) x (1, 0, 0) in component "METAL cap 01"
sketch "M5 clearance sketch (2)" plane through (0, 0, -2) normal (0, 0, 1) x (1, 0, 0) in component "METAL cap 01"
  circle A0 centre (12, 120) radius 2.75
  dimension "d784" = 12
  dimension "d785" = 120
  dimension "d786" = 5.5
  measures "d784" horizontal distance of origin A0.centre
  measures "d785" vertical distance of origin A0.centre
  measures "d786" diameter of A0
extrude "M5 clearance'" cut sketch "M5 clearance sketch (2)" along normal blind 2 bodies 21 in component "METAL cap 01"
ref_plane "WorkPlane1" through (0, 0, 5) normal (0, 0, 1) x (1, 0, 0) in component "PRINT rear bearing seat 01"
sketch "Rear bearing seat sketch (2)" plane through (0, 0, 5) normal (0, 0, 1) x (1, 0, 0) in component "PRINT rear bearing seat 01"
  circle A0 centre (12, 120) radius 9
  dimension "d791" = 12
  dimension "d792" = 120
  dimension "d793" = 18
  measures "d791" horizontal distance of origin A0.centre
  measures "d792" vertical distance of origin A0.centre
  measures "d793" diameter of A0
extrude "Rear bearing seat'" add sketch "Rear bearing seat sketch (2)" along normal blind 2 separate body makes body 22 in component "PRINT rear bearing seat 01"
ref_plane "WorkPlane2" through (0, 0, 5) normal (0, 0, 1) x (1, 0, 0) in component "PRINT rear bearing seat 01"
sketch "Shoulder clearance sketch (2)" plane through (0, 0, 5) normal (0, 0, 1) x (1, 0, 0) in component "PRINT rear bearing seat 01"
  circle A0 centre (12, 120) radius 4.2
  dimension "d798" = 12
  dimension "d799" = 120
  dimension "d800" = 8.4
  measures "d798" horizontal distance of origin A0.centre
  measures "d799" vertical distance of origin A0.centre
  measures "d800" diameter of A0
extrude "Shoulder clearance'" cut sketch "Shoulder clearance sketch (2)" along normal blind 2 bodies 22 in component "PRINT rear bearing seat 01"
sketch "8 mm shoulder sketch (2)" plane through (0, 0, 0) normal (0, 0, 1) x (1, 0, 0) in component "METAL stepped compression spacer 01"
  circle A0 centre (12, 120) radius 4
  dimension "d803" = 12
  dimension "d804" = 120
  dimension "d805" = 8
  measures "d803" horizontal distance of origin A0.centre
  measures "d804" vertical distance of origin A0.centre
  measures "d805" diameter of A0
extrude "8 mm shoulder'" add sketch "8 mm shoulder sketch (2)" along normal blind 7 separate body makes body 23 in component "METAL stepped compression spacer 01"
ref_plane "WorkPlane1" through (0, 0, 7) normal (0, 0, 1) x (1, 0, 0) in component "METAL stepped compression spacer 01"
sketch "12 mm base sketch (2)" plane through (0, 0, 7) normal (0, 0, 1) x (1, 0, 0) in component "METAL stepped compression spacer 01"
  circle A0 centre (12, 120) radius 6
  dimension "d810" = 12
  dimension "d811" = 120
  dimension "d812" = 12
  measures "d810" horizontal distance of origin A0.centre
  measures "d811" vertical distance of origin A0.centre
  measures "d812" diameter of A0
extrude "12 mm base'" add sketch "12 mm base sketch (2)" along normal blind 8 bodies 23 in component "METAL stepped compression spacer 01"
sketch "Through bore sketch (2)" plane through (0, 0, 0) normal (0, 0, 1) x (1, 0, 0) in component "METAL stepped compression spacer 01"
  circle A0 centre (12, 120) radius 2.75
  dimension "d815" = 12
  dimension "d816" = 120
  dimension "d817" = 5.5
  measures "d815" horizontal distance of origin A0.centre
  measures "d816" vertical distance of origin A0.centre
  measures "d817" diameter of A0
extrude "Through bore'" cut sketch "Through bore sketch (2)" along normal blind 15 bodies 23 in component "METAL stepped compression spacer 01"
ref_plane "WorkPlane1" through (0, 0, -5) normal (0, 0, 1) x (1, 0, 0) in component "REFERENCE M5 screw 01 - length follows stack"
sketch "Nominal button head sketch (2)" plane through (0, 0, -5) normal (0, 0, 1) x (1, 0, 0) in component "REFERENCE M5 screw 01 - length follows stack"
  circle A0 centre (12, 120) radius 4.75
  dimension "d822" = 12
  dimension "d823" = 120
  dimension "d824" = 9.5
  measures "d822" horizontal distance of origin A0.centre
  measures "d823" vertical distance of origin A0.centre
  measures "d824" diameter of A0
extrude "Nominal button head'" add sketch "Nominal button head sketch (2)" along normal blind 3 separate body makes body 24 in component "REFERENCE M5 screw 01 - length follows stack"
ref_plane "WorkPlane2" through (0, 0, -2) normal (0, 0, 1) x (1, 0, 0) in component "REFERENCE M5 screw 01 - length follows stack"
sketch "Unthreaded shank envelope sketch (2)" plane through (0, 0, -2) normal (0, 0, 1) x (1, 0, 0) in component "REFERENCE M5 screw 01 - length follows stack"
  circle A0 centre (12, 120) radius 2.5
  dimension "d829" = 12
  dimension "d830" = 120
  dimension "d831" = 5
  measures "d829" horizontal distance of origin A0.centre
  measures "d830" vertical distance of origin A0.centre
  measures "d831" diameter of A0
extrude "Unthreaded shank envelope'" add sketch "Unthreaded shank envelope sketch (2)" along normal blind 22 bodies 24 in component "REFERENCE M5 screw 01 - length follows stack"
ref_plane "WorkPlane1" through (0, 0, 17) normal (0, 0, 1) x (1, 0, 0) in component "REFERENCE M5 slot-6 T nut 01"
sketch "T nut envelope sketch (2)" plane through (0, 0, 17) normal (0, 0, 1) x (1, 0, 0) in component "REFERENCE M5 slot-6 T nut 01"
  line L0 (7.2, 115) -> (16.8, 115)
  line L1 (16.8, 115) -> (16.8, 125)
  line L2 (16.8, 125) -> (7.2, 125)
  line L3 (7.2, 125) -> (7.2, 115)
  dimension "d836" = 7.2
  dimension "d837" = 115
  dimension "d838" = 9.6
  dimension "d839" = 10
  constraint horizontal L0
  constraint vertical L1
  constraint horizontal L2
  constraint vertical L3
  measures "d836" horizontal distance of origin L0.start
  measures "d837" vertical distance of origin L0.start
  measures "d838" horizontal distance of L0.start L0.end
  measures "d839" vertical distance of L0.end L1.end
extrude "T nut envelope'" add sketch "T nut envelope sketch (2)" along normal blind 4 separate body makes body 25 in component "REFERENCE M5 slot-6 T nut 01"
ref_plane "WorkPlane2" through (0, 0, 17) normal (0, 0, 1) x (1, 0, 0) in component "REFERENCE M5 slot-6 T nut 01"
sketch "Thread envelope sketch (2)" plane through (0, 0, 17) normal (0, 0, 1) x (1, 0, 0) in component "REFERENCE M5 slot-6 T nut 01"
  circle A0 centre (12, 120) radius 2.6
  dimension "d844" = 12
  dimension "d845" = 120
  dimension "d846" = 5.2
  measures "d844" horizontal distance of origin A0.centre
  measures "d845" vertical distance of origin A0.centre
  measures "d846" diameter of A0
extrude "Thread envelope'" cut sketch "Thread envelope sketch (2)" along normal blind 4 bodies 24 in component "REFERENCE M5 screw 01 - length follows stack"
extrude "Extrude2'" cut sketch "Thread envelope sketch (2)" along normal blind 4 bodies 25 in component "REFERENCE M5 slot-6 T nut 01"
ref_plane "WorkPlane1" through (0, 0, -2) normal (0, 0, 1) x (1, 0, 0) in component "METAL cap 02"
sketch "Visible cap sketch (3)" plane through (0, 0, -2) normal (0, 0, 1) x (1, 0, 0) in component "METAL cap 02"
  circle A0 centre (12, 228) radius 9
  dimension "d853" = 12
  dimension "d854" = 228
  dimension "d855" = 18
  measures "d853" horizontal distance of origin A0.centre
  measures "d854" vertical distance of origin A0.centre
  measures "d855" diameter of A0
extrude "Visible cap''" add sketch "Visible cap sketch (3)" along normal blind 2 separate body makes body 26 in component "METAL cap 02"
ref_plane "WorkPlane2" through (0, 0, -2) normal (0, 0, 1) x (1, 0, 0) in component "METAL cap 02"
sketch "M5 clearance sketch (3)" plane through (0, 0, -2) normal (0, 0, 1) x (1, 0, 0) in component "METAL cap 02"
  circle A0 centre (12, 228) radius 2.75
  dimension "d860" = 12
  dimension "d861" = 228
  dimension "d862" = 5.5
  measures "d860" horizontal distance of origin A0.centre
  measures "d861" vertical distance of origin A0.centre
  measures "d862" diameter of A0
extrude "M5 clearance''" cut sketch "M5 clearance sketch (3)" along normal blind 2 bodies 26 in component "METAL cap 02"
ref_plane "WorkPlane1" through (0, 0, 5) normal (0, 0, 1) x (1, 0, 0) in component "PRINT rear bearing seat 02"
sketch "Rear bearing seat sketch (3)" plane through (0, 0, 5) normal (0, 0, 1) x (1, 0, 0) in component "PRINT rear bearing seat 02"
  circle A0 centre (12, 228) radius 9
  dimension "d867" = 12
  dimension "d868" = 228
  dimension "d869" = 18
  measures "d867" horizontal distance of origin A0.centre
  measures "d868" vertical distance of origin A0.centre
  measures "d869" diameter of A0
extrude "Rear bearing seat''" add sketch "Rear bearing seat sketch (3)" along normal blind 2 separate body makes body 27 in component "PRINT rear bearing seat 02"
ref_plane "WorkPlane2" through (0, 0, 5) normal (0, 0, 1) x (1, 0, 0) in component "PRINT rear bearing seat 02"
sketch "Shoulder clearance sketch (3)" plane through (0, 0, 5) normal (0, 0, 1) x (1, 0, 0) in component "PRINT rear bearing seat 02"
  circle A0 centre (12, 228) radius 4.2
  dimension "d874" = 12
  dimension "d875" = 228
  dimension "d876" = 8.4
  measures "d874" horizontal distance of origin A0.centre
  measures "d875" vertical distance of origin A0.centre
  measures "d876" diameter of A0
extrude "Shoulder clearance''" cut sketch "Shoulder clearance sketch (3)" along normal blind 2 bodies 27 in component "PRINT rear bearing seat 02"
sketch "8 mm shoulder sketch (3)" plane through (0, 0, 0) normal (0, 0, 1) x (1, 0, 0) in component "METAL stepped compression spacer 02"
  circle A0 centre (12, 228) radius 4
  dimension "d879" = 12
  dimension "d880" = 228
  dimension "d881" = 8
  measures "d879" horizontal distance of origin A0.centre
  measures "d880" vertical distance of origin A0.centre
  measures "d881" diameter of A0
extrude "8 mm shoulder''" add sketch "8 mm shoulder sketch (3)" along normal blind 7 separate body makes body 28 in component "METAL stepped compression spacer 02"
ref_plane "WorkPlane1" through (0, 0, 7) normal (0, 0, 1) x (1, 0, 0) in component "METAL stepped compression spacer 02"
sketch "12 mm base sketch (3)" plane through (0, 0, 7) normal (0, 0, 1) x (1, 0, 0) in component "METAL stepped compression spacer 02"
  circle A0 centre (12, 228) radius 6
  dimension "d886" = 12
  dimension "d887" = 228
  dimension "d888" = 12
  measures "d886" horizontal distance of origin A0.centre
  measures "d887" vertical distance of origin A0.centre
  measures "d888" diameter of A0
extrude "12 mm base''" add sketch "12 mm base sketch (3)" along normal blind 8 bodies 28 in component "METAL stepped compression spacer 02"
sketch "Through bore sketch (3)" plane through (0, 0, 0) normal (0, 0, 1) x (1, 0, 0) in component "METAL stepped compression spacer 02"
  circle A0 centre (12, 228) radius 2.75
  dimension "d891" = 12
  dimension "d892" = 228
  dimension "d893" = 5.5
  measures "d891" horizontal distance of origin A0.centre
  measures "d892" vertical distance of origin A0.centre
  measures "d893" diameter of A0
extrude "Through bore''" cut sketch "Through bore sketch (3)" along normal blind 15 bodies 28 in component "METAL stepped compression spacer 02"
ref_plane "WorkPlane1" through (0, 0, -5) normal (0, 0, 1) x (1, 0, 0) in component "REFERENCE M5 screw 02 - length follows stack"
sketch "Nominal button head sketch (3)" plane through (0, 0, -5) normal (0, 0, 1) x (1, 0, 0) in component "REFERENCE M5 screw 02 - length follows stack"
  circle A0 centre (12, 228) radius 4.75
  dimension "d898" = 12
  dimension "d899" = 228
  dimension "d900" = 9.5
  measures "d898" horizontal distance of origin A0.centre
  measures "d899" vertical distance of origin A0.centre
  measures "d900" diameter of A0
extrude "Nominal button head''" add sketch "Nominal button head sketch (3)" along normal blind 3 separate body makes body 29 in component "REFERENCE M5 screw 02 - length follows stack"
ref_plane "WorkPlane2" through (0, 0, -2) normal (0, 0, 1) x (1, 0, 0) in component "REFERENCE M5 screw 02 - length follows stack"
sketch "Unthreaded shank envelope sketch (3)" plane through (0, 0, -2) normal (0, 0, 1) x (1, 0, 0) in component "REFERENCE M5 screw 02 - length follows stack"
  circle A0 centre (12, 228) radius 2.5
  dimension "d905" = 12
  dimension "d906" = 228
  dimension "d907" = 5
  measures "d905" horizontal distance of origin A0.centre
  measures "d906" vertical distance of origin A0.centre
  measures "d907" diameter of A0
extrude "Unthreaded shank envelope''" add sketch "Unthreaded shank envelope sketch (3)" along normal blind 22 bodies 29 in component "REFERENCE M5 screw 02 - length follows stack"
ref_plane "WorkPlane1" through (0, 0, 17) normal (0, 0, 1) x (1, 0, 0) in component "REFERENCE M5 slot-6 T nut 02"